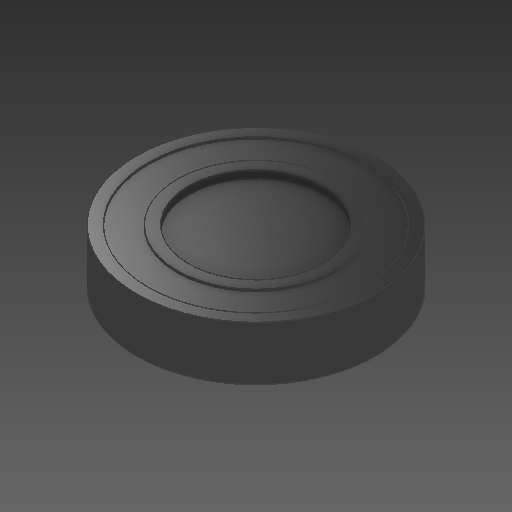
# Autodesk Inventor part: Bearing-Turbine
Saved by Autodesk Inventor 2026.1 (Build 301233020, 233B)
## iProperties
Created: 2026-10-21
Part Number: Bearing-Turbine
Material: Generic
Document SubType Name: Modeling
Designer: YmCris
Density: 1 g/cm^3
Appearance: Default
Author: YmCris
Autodesk Inventor part; units mm, degrees
sketch "Sketch1" plane through (0, 0, 0) normal (0, 1, 0) x (-1, 0, 0)
  circle A0 centre (0, 0) radius 17.5
  circle A1 centre (0, 0) radius 20.5
  circle A2 centre (0, 0) radius 28
  circle A3 centre (0, 0) radius 31
  dimension "d0" = 35
  dimension "d1" = 41
  dimension "d2" = 56
  dimension "d3" = 62
  constraints: 4 centre point, 4 coincident
  measures "d0" diameter of A0
  measures "d1" diameter of A1
  measures "d2" diameter of A2
  measures "d3" diameter of A3
extrude "Extrusion1" add sketch "Sketch1" along normal blind 14
ref_plane "Work Plane1" through (0, 7, 0) normal (0, -1, 0) x (1, 0, 0)
sketch "Sketch2" plane through (0, 7, 0) normal (0, -1, 0) x (1, 0, 0)
  circle A0 centre (-24.25, 0) radius 3.75
  circle A1 centre (0, 0) radius 20.5
  circle A2 centre (-22.787546, -8.293988) radius 3.75
  circle A3 centre (-18.576578, -15.5876) radius 3.75
  circle A4 centre (-12.125, -21.001116) radius 3.75
  circle A5 centre (-4.210968, -23.881588) radius 3.75
  circle A6 centre (4.210968, -23.881588) radius 3.75
  circle A7 centre (12.125, -21.001116) radius 3.75
  circle A8 centre (18.576578, -15.5876) radius 3.75
  circle A9 centre (22.787546, -8.293988) radius 3.75
  circle A10 centre (24.25, 0) radius 3.75
  circle A11 centre (22.787546, 8.293988) radius 3.75
  circle A12 centre (18.576578, 15.5876) radius 3.75
  circle A13 centre (12.125, 21.001116) radius 3.75
  circle A14 centre (4.210968, 23.881588) radius 3.75
  circle A15 centre (-4.210968, 23.881588) radius 3.75
  circle A16 centre (-12.125, 21.001116) radius 3.75
  circle A17 centre (-18.576578, 15.5876) radius 3.75
  circle A18 centre (-22.787546, 8.293988) radius 3.75
  point P0 (-19.263699, 7.011413)
  point P1 (-15.703911, 13.177146)
  point P2 (-10.25, 17.753521)
  point P3 (-3.559788, 20.188559)
  point P4 (3.559788, 20.188559)
  point P5 (10.25, 17.753521)
  point P6 (15.703911, 13.177146)
  point P7 (19.263699, 7.011413)
  point P8 (20.5, 0)
  point P9 (19.263699, -7.011413)
  point P10 (15.703911, -13.177146)
  point P11 (10.25, -17.753521)
  point P12 (3.559788, -20.188559)
  point P13 (-3.559788, -20.188559)
  point P14 (-10.25, -17.753521)
  point P15 (-15.703911, -13.177146)
  point P16 (-19.263699, -7.011413)
  point P17 (-20.5, 0)
  dimension "d9" = 360
  constraints: 18 centre point, 1 tangent, 37 other
extrude "Extrusion2" add sketch "Sketch2" along normal mid plane 10
ref_plane "Work Plane2" through (0, 13, 0) normal (0, -1, 0) x (1, 0, 0)
sketch "Sketch3" plane through (0, 13, 0) normal (0, -1, 0) x (1, 0, 0)
  circle A0 centre (0, 0) radius 20.5
  circle A1 centre (0, 0) radius 28
  constraints: 2 centre point, 2 coincident
extrude "Extrusion3" add sketch "Sketch3" along normal mid plane 1
ref_plane "Work Plane3" through (0, 2, 0) normal (0, -1, 0) x (1, 0, 0)
sketch "Sketch4" plane through (0, 2, 0) normal (0, -1, 0) x (1, 0, 0)
  point P0 (0, 0)
sketch "Sketch5" plane through (0, 2, 0) normal (0, -1, 0) x (1, 0, 0)
  circle A0 centre (0, 0) radius 20.5
  circle A1 centre (0, 0) radius 28
  constraints: 2 centre point, 2 coincident
extrude "Extrusion4" add sketch "Sketch5" along normal blind 1
body "Solid1"
